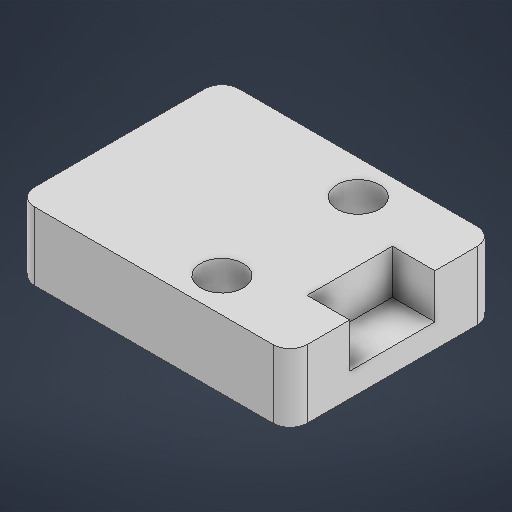
# Autodesk Inventor part: hall effect sensor
Saved by Autodesk Inventor 2026.2 (Build 302298010, 298A)
## iProperties
Created: 2026-07-16
Part Number: hall effect sensor
Material: Generic
Document SubType Name: Modeling
Designer: User
Density: 1 g/cm^3
Appearance: Default
Author: User
Autodesk Inventor part; units mm, degrees
ref_plane "YZ Plane" through (0, 0, 0) normal (1, 0, 0) x (0, 1, 0)
ref_plane "XZ Plane" through (0, 0, 0) normal (0, 1, 0) x (-1, 0, 0)
ref_plane "XY Plane" through (0, 0, 0) normal (0, 0, 1) x (1, 0, 0)
sketch "Sketch1" plane through (0, 0, 0) normal (0, 1, 0) x (-1, 0, 0)
  line L0 (0, 0) -> (32, 0)
  line L1 (32, 0) -> (32, -24)
  line L2 (32, -24) -> (0, -24)
  line L3 (0, -24) -> (0, 0)
  dimension "d0" = 32
  dimension "d1" = 24
  constraints: 8 end point, 2 parallel, 1 horizontal, 1 perpendicular
  measures "d0" distance of L1.end L2.end
  measures "d1" distance of L0.end L1.end
extrude "Extrusion1" add sketch "Sketch1" along normal blind 8
sketch "Sketch2" plane through (0, 0, 0) normal (1, 0, 0) x (0, 0, -1)
  line L0 (24, 8) -> (0, 8) projected
  line L1 (12, 8) -> (17, 8)
  line L2 (12, 8) -> (7, 8)
  line L3 (7, 8) -> (7, 2.8)
  line L4 (7, 2.8) -> (17, 2.8)
  line L5 (17, 2.8) -> (17, 8)
  point P0 (0, 0)
  dimension "d4" = 5
  dimension "d5" = 5
  dimension "d6" = 5.2
  constraints: 10 end point, 3 perpendicular, 2 point on line, 1 midpoint
  measures "d4" distance of L1.start L1.end
  measures "d5" distance of L1.start L2.end
  measures "d6" distance of L2.end L3.end
extrude "Extrusion2" cut sketch "Sketch2" against normal blind 5
fillet "Fillet1" radius 2 4 edges at (0, 4, 0) (0, 4, -24) (-32, 4, 0) (-32, 4, -24)
sketch "Sketch3" plane through (0, 8, 0) normal (0, 1, 0) x (1, 0, 0)
  line L0 (0, 0) -> (-12, 0)
  line L1 (-12, 0) -> (-12, 4)
  line L2 (0, 24) -> (-12, 24)
  line L3 (-12, 24) -> (-12, 20)
  dimension "d10" = 12
  dimension "d11" = 4
  dimension "d12" = 12
  dimension "d13" = 4
  constraints: 8 end point, 2 coincident, 2 horizontal, 2 perpendicular
  measures "d10" distance of L0.start L0.end
  measures "d11" distance of L0.end L1.end
  measures "d12" distance of L2.start L2.end
  measures "d13" distance of L2.end L3.end
hole "Hole1" at (-12, 8, -4) at (-12, 8, -20) direction (0, -1, 0) diameter 5 end through all
body "Solid1"
